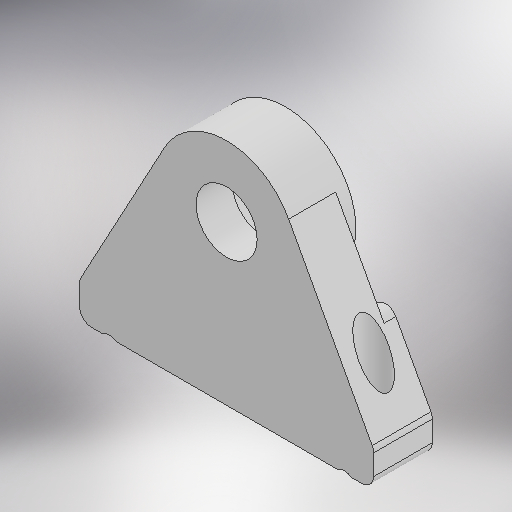
# Autodesk Inventor part: AP5.0_base-bearing-fix
Saved by Autodesk Inventor 2025.3 (Build 293356030, 356C)
## iProperties
Created: 2026-02-11
Part Number: AP5.0_base-bearing-fix
Material: 一般
Document SubType Name: Sheet Metal
Designer: ibuki_ono
Density: 1 g/cm^3
Sheet Metal Rule: Default_mm
Appearance: 既定
Author: ibuki_ono
Autodesk Inventor part; units mm, degrees
ref_plane "YZ Plane" through (0, 0, 0) normal (1, 0, 0) x (0, 1, 0)
ref_plane "XZ Plane" through (0, 0, 0) normal (0, 1, 0) x (-1, 0, 0)
ref_plane "XY Plane" through (0, 0, 0) normal (0, 0, 1) x (1, 0, 0)
sketch "スケッチ1" plane through (0, 0, 0) normal (0, 0, 1) x (1, 0, 0)
  circle A0 centre (0, 0) radius 6
  line L0 (-12.5, -13.5) -> (12.5, -13.5)
  line L1 (12.5, -13.5) -> (12.5, -10.5)
  line L2 (12.5, -10.5) -> (-12.5, -10.5)
  line L3 (-12.5, -10.5) -> (-12.5, -13.5)
  line L4 (-12.5, -13.5) -> (12.5, -10.5) construction
  line L5 (12.5, -13.5) -> (-12.5, -10.5) construction
  line L6 (-12.5, -10.5) -> (-5.2776, 2.8543)
  line L7 (5.2776, 2.8543) -> (12.5, -10.5)
  point P0 (0, -12)
  dimension "d0" = 12
  dimension "d1" = 25
  dimension "d2" = 3
  dimension "d3" = 13.5
  measures "d0" diameter of A0
  measures "d1" distance of L2.end L1.end
  measures "d2" distance of L1.end L0.end
  measures "d3" distance from line of point (0, 0) L0
extrude "プレート1" add sketch "スケッチ1" along normal blind 5
sketch "スケッチ2" plane through (0, 0, 0) normal (0, 0, -1) x (-1, 0, 0)
  circle A0 centre (0, 0) radius 4
  dimension "d5" = 8
  constraints: 1 centre point, 1 coincident
  measures "d5" diameter of A0
extrude "押し出し1" cut sketch "スケッチ2" against normal blind 1.9
sketch "スケッチ3" plane through (0, 0, 0) normal (0, 0, -1) x (-1, 0, 0)
  line L0 (-12.5, -10.5) -> (-5.2776, 2.8543) projected
  line L1 (5.2776, 2.8543) -> (12.5, -10.5) projected
  arc A0 (5.2776, 2.8543) -> (-5.2776, 2.8543) centre (0, 0) ccw projected
  circle A1 centre (0, 0) radius 6
  circle A2 centre (0, 0) radius 9
  point P0 (-8.4688, -3.0463)
  point P1 (8.4688, -3.0463)
  dimension "d8" = 18
  constraints: 2 centre point, 2 coincident, 1 concentric
  measures "d8" diameter of A2
extrude "押し出し2" cut sketch "スケッチ3" against normal blind 1 contours L0 A1 L1 A2
fillet "フィレット1" radius 1 2 edges at (8.4688, -3.0463, 0.5) (-8.4688, -3.0463, 0.5)
sketch "スケッチ4" plane through (0, 0, 0) normal (0, 0, -1) x (-1, 0, 0)
  line L0 (12.5, -13.5) -> (-12.5, -13.5) projected
  circle A0 centre (-10, -14.35) radius 1.05
  circle A1 centre (10, -14.35) radius 1.05
  point P0 (0, 0)
  point P1 (0, -13.5)
  point P2 (0, -13.5)
  point P3 (9.3836, -13.5)
  point P4 (10.6164, -13.5)
  point P5 (-10.6164, -13.5)
  point P6 (-9.3836, -13.5)
  dimension "d12" = 2.1
  dimension "d13" = 2.1
  dimension "d14" = 0.85
  dimension "d15" = 0.85
  dimension "d16" = 10
  dimension "d17" = 10
  constraints: 2 centre point, 2 midpoint
  measures "d12" diameter of A0
  measures "d13" diameter of A1
  measures "d14" distance from line of A0.centre L0
  measures "d15" distance from line of L0 A1.centre
  measures "d16" horizontal distance of point (0, -13.5) A0.centre
  measures "d17" horizontal distance of point (0, -13.5) A1.centre
extrude "押し出し3" cut sketch "スケッチ4" against normal through all contours L0 A1 | L0 A0 picked at (9.8578, -13.4635) picked at (-10.1422, -13.4635)
sketch "スケッチ5" plane through (-9.3836, -13.5, 0) normal (0, -1, 0) x (1, 0, 0)
  line L0 (18.7671, 5) -> (20, 5) projected
  line L1 (18.7671, 0) -> (18.7671, 5) projected
  line L2 (20, 0) -> (18.7671, 0) projected
  line L3 (20, 5) -> (20, 0) projected
  line L4 (-1.2329, 5) -> (0, 5) projected
  line L5 (-1.2329, 0) -> (-1.2329, 5) projected
  line L6 (0, 0) -> (-1.2329, 0) projected
  line L7 (0, 5) -> (0, 0) projected
  line L8 (19.3836, 0) -> (19.3836, 5) construction
  line L9 (-0.6164, 5) -> (-0.6164, 0) construction
  point P0 (9.3836, 0)
  point P1 (-0.6164, 2.5)
  point P2 (19.3836, 2.5)
  constraints: 6 midpoint, 4 end point
hole "穴1" at (-10, -13.5, 2.5) at (10, -13.5, 2.5) direction (0, 1, 0) diameter 2.5 end through all
fillet "フィレット2" radius 1 4 edges at (12.5, -13.5, 2.5) (12.5, -10.5, 2.5) (-12.5, -13.5, 2.5) (-12.5, -10.5, 2.5)
sketch "スケッチ6" plane through (0, 0, 5) normal (0, 0, 1) x (1, 0, 0)
  arc A0 (5.2776, 2.8543) -> (-5.2776, 2.8543) centre (0, 0) ccw projected
hole "穴2" at (0, 0, 5) direction (0, 0, -1) diameter 5.2 end through all
equation "\"d15\" = d14"
equation "\"d17\" = d16"
equation "\"d25\" = Thickness"
equation "\"d4\" = Thickness"
equation "\"BendRadius\" = Thickness"
equation "\"BendReliefWidth\" = Thickness"
equation "\"BendReliefDepth\" = 0.5 * Thickness"
equation "\"TransitionRadius\" = BendRadius"
equation "\"JacobiRadiusSize\" = BendRadius"
equation "\"GapSize\" = Thickness"
equation "\"Thickness\" = 5"
